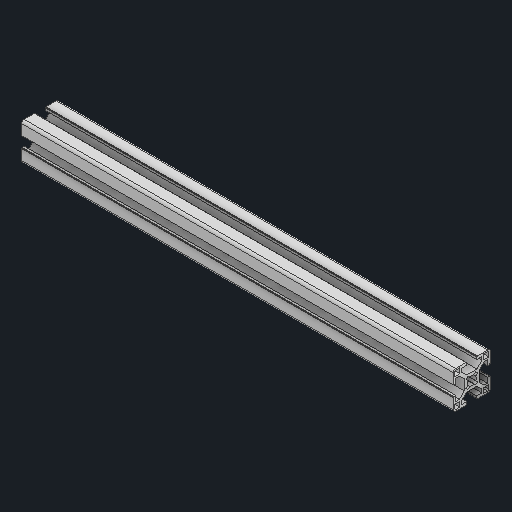
# Autodesk Inventor part: 3842993703_STRUT PROFILE 30x30_h150_260914140700468
Saved by Autodesk Inventor 2026 (Build 300175050, 175E)
## iProperties
Created: 2026-07-03
Material: Generic
Document SubType Name: Modeling
Designer: Anura
Density: 1 g/cm^3
Appearance: Default
Catalog Web Link: www.boschrexroth.com/brl
Description: STRUT PROFILE 30x30
Vendor: Bosch Rexroth AG - BRL
Mass: 315 g
Package size: 1
Material no.: 3842993703.0
Part name: STRUT PROFILE 30x30
Parameters: LP=350MM;
Weight: 0.315
Product group: MGE
HS code: 76109090.0
Format Version: 0
MTproCodeNo: 76109090.0
MTproDesignation: STRUT PROFILE 30x30
MTproParam1: 2#0@Profile type=30x30|Length L [mm]=350|Number of finishes=0|
MtproPline: 20
MTproPrice: 0.0
MTproWeight: 0.315
MtproWeightUnit: kg/m
Major Version: 4
Minor Version: 0
OrderNo: 3842993703.0
Param: LP=350MM;
ProductId: Bosch Rexroth AG
Sending System: Bosch Rexroth AG
FileDetail: HD
Author: Anura
Autodesk Inventor part; units mm, degrees
ref_plane "YZ Plane" through (0, 0, 0) normal (1, 0, 0) x (0, 1, 0)
ref_plane "XZ Plane" through (0, 0, 0) normal (0, 1, 0) x (-1, 0, 0)
ref_plane "XY Plane" through (0, 0, 0) normal (0, 0, 1) x (1, 0, 0)
sketch "Sketch1" plane through (0, 0, 0) normal (1, 0, 0) x (0, 1, 0)
  line L0 (-9.7, 13.85) -> (-12.85, 13.85)
  arc A0 (-12.85, 13.85) -> (-13.85, 12.85) centre (-12.85, 12.85) ccw
  line L1 (-13.85, 12.85) -> (-13.85, 9.7)
  line L2 (-13.85, 9.7) -> (-9.7, 9.7)
  line L3 (-9.7, 9.7) -> (-9.7, 13.85)
  line L4 (-13.85, -9.7) -> (-13.85, -12.85)
  arc A1 (-13.85, -12.85) -> (-12.85, -13.85) centre (-12.85, -12.85) ccw
  line L5 (-12.85, -13.85) -> (-9.7, -13.85)
  line L6 (-9.7, -13.85) -> (-9.7, -9.7)
  line L7 (-9.7, -9.7) -> (-13.85, -9.7)
  line L8 (9.7, -13.85) -> (12.85, -13.85)
  arc A2 (12.85, -13.85) -> (13.85, -12.85) centre (12.85, -12.85) ccw
  line L9 (13.85, -12.85) -> (13.85, -9.7)
  line L10 (13.85, -9.7) -> (9.7, -9.7)
  line L11 (9.7, -9.7) -> (9.7, -13.85)
  line L12 (13.85, 9.7) -> (13.85, 12.85)
  arc A3 (13.85, 12.85) -> (12.85, 13.85) centre (12.85, 12.85) ccw
  line L13 (12.85, 13.85) -> (9.7, 13.85)
  line L14 (9.7, 13.85) -> (9.7, 9.7)
  line L15 (9.7, 9.7) -> (13.85, 9.7)
  arc A4 (1.6168, 3.2724) -> (-1.6168, 3.2724) centre (0, 0) ccw
  line L16 (-1.6168, 3.2724) -> (-3.1877, 4.5905)
  line L17 (-3.1877, 4.5905) -> (-4.5905, 3.1877)
  line L18 (-4.5905, 3.1877) -> (-3.2724, 1.6168)
  arc A5 (-3.2724, 1.6168) -> (-3.2724, -1.6168) centre (0, 0) ccw
  line L19 (-3.2724, -1.6168) -> (-4.5905, -3.1877)
  line L20 (-4.5905, -3.1877) -> (-3.1877, -4.5905)
  line L21 (-3.1877, -4.5905) -> (-1.6168, -3.2724)
  arc A6 (-1.6168, -3.2724) -> (1.6168, -3.2724) centre (0, 0) ccw
  line L22 (1.6168, -3.2724) -> (3.1877, -4.5905)
  line L23 (3.1877, -4.5905) -> (4.5905, -3.1877)
  line L24 (4.5905, -3.1877) -> (3.2724, -1.6168)
  arc A7 (3.2724, -1.6168) -> (3.2724, 1.6168) centre (0, 0) ccw
  line L25 (3.2724, 1.6168) -> (4.5905, 3.1877)
  line L26 (4.5905, 3.1877) -> (3.1877, 4.5905)
  line L27 (3.1877, 4.5905) -> (1.6168, 3.2724)
  line L28 (4.1969, 6) -> (8.25, 10.0531)
  line L29 (8.25, 10.0531) -> (8.25, 12.8)
  line L30 (8.25, 12.8) -> (4.05, 12.8)
  line L31 (4.05, 12.8) -> (4.05, 14.5)
  line L32 (4.05, 14.5) -> (4.55, 14.5)
  line L33 (4.55, 14.5) -> (4.55, 15)
  line L34 (4.55, 15) -> (13, 15)
  arc A8 (15, 13) -> (13, 15) centre (13, 13) ccw
  line L35 (15, 13) -> (15, 4.55)
  line L36 (15, 4.55) -> (14.5, 4.55)
  line L37 (14.5, 4.55) -> (14.5, 4.05)
  line L38 (14.5, 4.05) -> (12.8, 4.05)
  line L39 (12.8, 4.05) -> (12.8, 8.25)
  line L40 (12.8, 8.25) -> (10.0531, 8.25)
  line L41 (10.0531, 8.25) -> (6, 4.1969)
  line L42 (6, 4.1969) -> (6, -4.1969)
  line L43 (6, -4.1969) -> (10.0531, -8.25)
  line L44 (10.0531, -8.25) -> (12.8, -8.25)
  line L45 (12.8, -8.25) -> (12.8, -4.05)
  line L46 (12.8, -4.05) -> (14.5, -4.05)
  line L47 (14.5, -4.05) -> (14.5, -4.55)
  line L48 (14.5, -4.55) -> (15, -4.55)
  line L49 (15, -4.55) -> (15, -13)
  arc A9 (13, -15) -> (15, -13) centre (13, -13) ccw
  line L50 (13, -15) -> (4.55, -15)
  line L51 (4.55, -15) -> (4.55, -14.5)
  line L52 (4.55, -14.5) -> (4.05, -14.5)
  line L53 (4.05, -14.5) -> (4.05, -12.8)
  line L54 (4.05, -12.8) -> (8.25, -12.8)
  line L55 (8.25, -12.8) -> (8.25, -10.0531)
  line L56 (8.25, -10.0531) -> (4.1969, -6)
  line L57 (4.1969, -6) -> (-4.1969, -6)
  line L58 (-4.1969, -6) -> (-8.25, -10.0531)
  line L59 (-8.25, -10.0531) -> (-8.25, -12.8)
  line L60 (-8.25, -12.8) -> (-4.05, -12.8)
  line L61 (-4.05, -12.8) -> (-4.05, -14.5)
  line L62 (-4.05, -14.5) -> (-4.55, -14.5)
  line L63 (-4.55, -14.5) -> (-4.55, -15)
  line L64 (-4.55, -15) -> (-13, -15)
  arc A10 (-15, -13) -> (-13, -15) centre (-13, -13) ccw
  line L65 (-15, -13) -> (-15, -4.55)
  line L66 (-15, -4.55) -> (-14.5, -4.55)
  line L67 (-14.5, -4.55) -> (-14.5, -4.05)
  line L68 (-14.5, -4.05) -> (-12.8, -4.05)
  line L69 (-12.8, -4.05) -> (-12.8, -8.25)
  line L70 (-12.8, -8.25) -> (-10.0531, -8.25)
  line L71 (-10.0531, -8.25) -> (-6, -4.1969)
  line L72 (-6, -4.1969) -> (-6, 4.1969)
  line L73 (-6, 4.1969) -> (-10.0531, 8.25)
  line L74 (-10.0531, 8.25) -> (-12.8, 8.25)
  line L75 (-12.8, 8.25) -> (-12.8, 4.05)
  line L76 (-12.8, 4.05) -> (-14.5, 4.05)
  line L77 (-14.5, 4.05) -> (-14.5, 4.55)
  line L78 (-14.5, 4.55) -> (-15, 4.55)
  line L79 (-15, 4.55) -> (-15, 13)
  arc A11 (-13, 15) -> (-15, 13) centre (-13, 13) ccw
  line L80 (-13, 15) -> (-4.55, 15)
  line L81 (-4.55, 15) -> (-4.55, 14.5)
  line L82 (-4.55, 14.5) -> (-4.05, 14.5)
  line L83 (-4.05, 14.5) -> (-4.05, 12.8)
  line L84 (-4.05, 12.8) -> (-8.25, 12.8)
  line L85 (-8.25, 12.8) -> (-8.25, 10.0531)
  line L86 (-8.25, 10.0531) -> (-4.1969, 6)
  line L87 (-4.1969, 6) -> (4.1969, 6)
  point P0 (0, 0)
  constraints: 176 end point, 24 point on circle, 12 centre point
extrude "BR_Extrude" add sketch "Sketch1" along normal blind 175 and the other way blind 175
equation "\"extrude_1\" = 0.5 * BR_WP5_BR_WP6_Length_090614421489026 + Start_delta"
equation "\"extrude_2\" = 0.5 * BR_WP5_BR_WP6_Length_090614421489026 + End_delta"
equation "\"Start_delta\" = 0"
equation "\"End_delta\" = 0"
equation "\"BR_WP5_BR_WP6_Length_090614421489026\" = 350"
body "Solid1"
